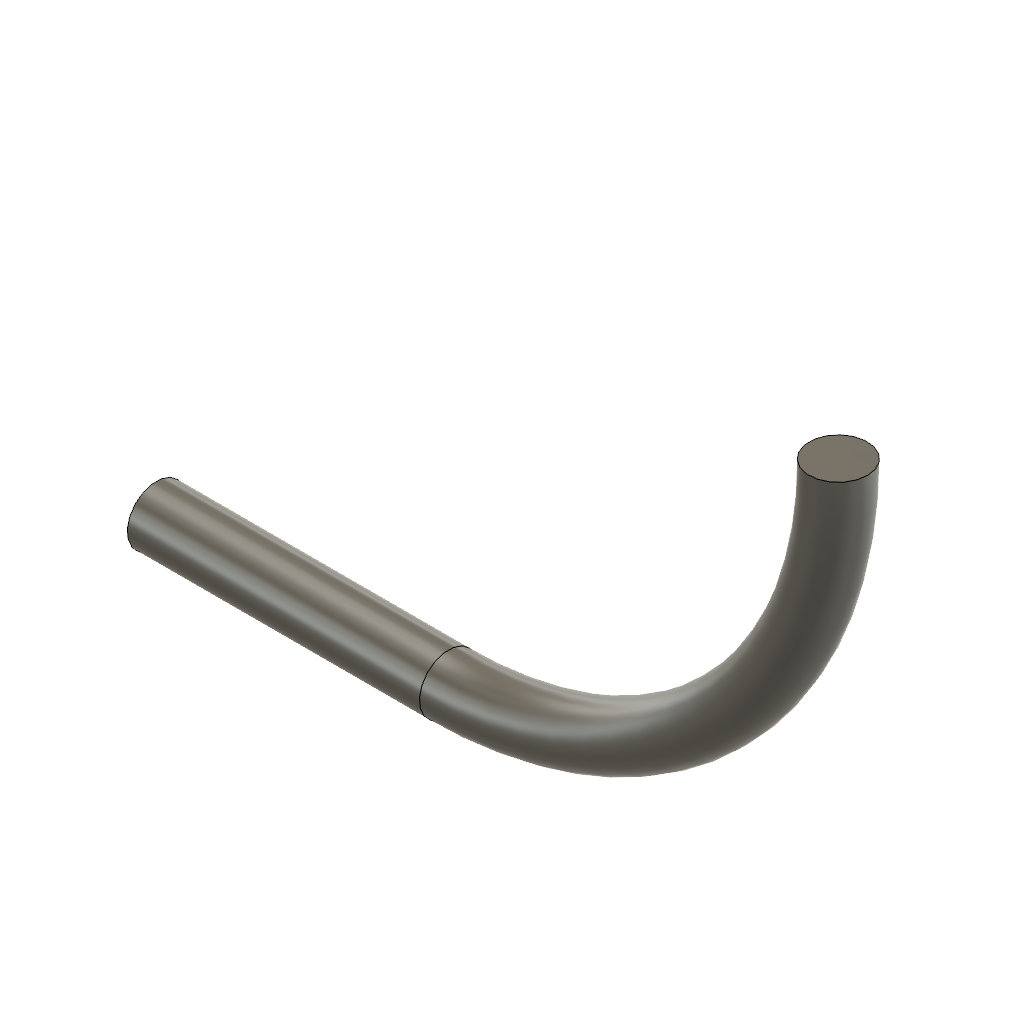
vendor_CompositeCircularControl (Autodesk Fusion 360 design; units mm, degrees)
part number: 2026-10-20-23-07-31-031
Autodesk Fusion 360 part; units mm, degrees
sketch "PipePathSketch" plane through (0, 0, 0) normal (0, 0, 1) x (1, 0, 0)
  line L0 (0, 0) -> (30, 0)
  arc A0 (30, 0) -> (70, 40) centre (30, 40) ccw
pipe "ProbePipePath" add diameter 6 path "PipePathSketch" along L0 A0
